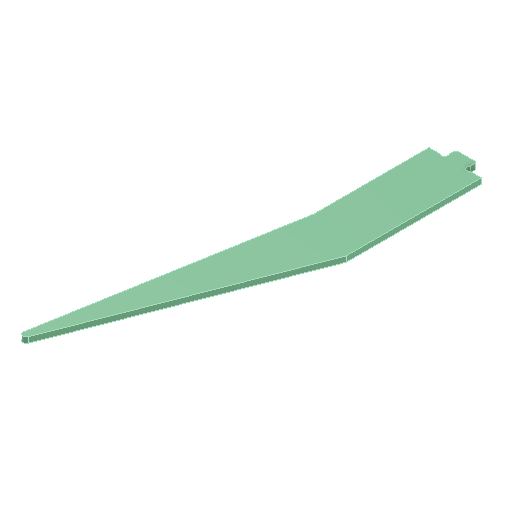
# Autodesk Inventor part: CUT_FR4_Stiffening_Rib_Top_Bot
Saved by Autodesk Inventor 2026.1 (Build 301233000, 233)
## iProperties
Created: 2025-11-04
Part Number: CUT_FR4_Stiffening_Rib_Top_Bot
Material: Generic
Document SubType Name: Modeling
Designer: User
Density: 1 g/cm^3
Appearance: Smooth - Dark Sea Green
Author: User
Autodesk Inventor part; units mm, degrees
ref_plane "YZ Plane" through (0, 0, 0) normal (1, 0, 0) x (0, 1, 0)
ref_plane "XZ Plane" through (0, 0, 0) normal (0, 1, 0) x (-1, 0, 0)
ref_plane "XY Plane" through (0, 0, 0) normal (0, 0, 1) x (1, 0, 0)
sketch "Sketch1" plane through (0, 0, 0) normal (0, 1, 0) x (-1, 0, 0)
  line L0 (0, 0) -> (0, -38.7)
  line L1 (0, -38.7) -> (15, -38.7)
  line L2 (0, 0) -> (34.716, 89.5031)
  line L3 (34.716, 89.5031) -> (48.7008, 84.0787)
  line L4 (48.7008, 84.0787) -> (15, -5.8115)
  line L5 (15, -5.8115) -> (15, -38.7)
  line L6 (15, -5.8115) -> (29.0906, 75)
  dimension "d0" = 38.7
  dimension "d1" = 15
  dimension "d2" = 158.8
  dimension "d3" = 96
  dimension "d4" = 15
  dimension "d5" = 96
  dimension "d8" = 75
  constraints: 14 end point, 2 perpendicular, 2 vertical, 1 point on line
  measures "d0" distance of L0.start L0.end
  measures "d1" distance of L0.end L1.end
  measures "d2" angle of L0 L2
  measures "d3" distance of L0.start L2.end
  measures "d4" distance of L2.end L3.end
  measures "d5" distance of L3.end L4.end
  measures "d8" vertical distance of L0.start L6.end
extrude "Extrusion1" add sketch "Sketch1" along normal blind 1.6 contours L2 L6 L5 L1 L0
fillet "Fillet1" radius 1 1 edges at (-29.0906, 0.8, 75)
sketch "Sketch2" plane through (0, 0, -38.7) normal (0, 0, -1) x (-1, 0, 0)
  line L0 (0, 1.6) -> (15, 1.6) construction
  line L1 (0, 0) -> (15, 0) construction
  line L2 (4.5, 1.6) -> (10.5, 1.6)
  line L3 (10.5, 1.6) -> (10.5, 0)
  line L4 (10.5, 0) -> (4.5, 0)
  line L5 (4.5, 0) -> (4.5, 1.6)
  dimension "d10" = 4.5
  dimension "d11" = 6
  constraints: 8 end point, 2 collinear, 2 parallel, 1 perpendicular
  measures "d10" distance from line of L5 L0.start
  measures "d11" distance between parallel lines of L3 L5
extrude "Extrusion2" add sketch "Sketch2" along normal blind 3.2
sketch "Sketch4" plane through (0, 1.6, 0) normal (0, 1, 0) x (1, 0, 0)
  line L0 (-10.5, 38.7) -> (-15, 38.7) construction
  line L1 (-10.5, 38.7) -> (-10.5, 41.9) construction
  circle A0 centre (-11.2071, 39.4071) radius 1
  line L2 (0, 38.7) -> (-4.5, 38.7) construction
  line L3 (-4.5, 38.7) -> (-4.5, 41.9) construction
  circle A1 centre (-3.7929, 39.4071) radius 1
  dimension "d15" = 2
  dimension "d17" = 2
  dimension "d14" = 45
  dimension "d16" = 45
  constraints: 2 coincident, 6 other
extrude "Extrusion3" cut sketch "Sketch4" against normal up to surface (1.6 mm away)
chamfer "Chamfer1" distance 0.5 angle 45 2 edges at (-4.5, 0.8, -41.9) (-10.5, 0.8, -41.9)
equation "\"d4\" = d1"
body "Solid1"
